Autodesk Fusion 360 part; units mm, degrees
(part 3 of 4)
sketch "Sketch2" plane through (0, 0, -3.5) normal (0, 0, -1) x (1, 0, 0)
  line L0 (7.3822, -60.9328) -> (7.3822, -58.9338)
  line L1 (7.3822, -58.9338) -> (21.3817, -58.9338)
  line L2 (21.3817, -58.9338) -> (21.3817, -60.9328)
  line L3 (21.3817, -60.9328) -> (22.1809, -60.9328)
  line L4 (22.1809, -60.9328) -> (22.1809, -64.0334)
  line L5 (22.1809, -64.0334) -> (21.3817, -64.0334)
  line L6 (21.3817, -64.0334) -> (21.3817, -69.8334)
  line L7 (21.3817, -69.8334) -> (22.1809, -69.8334)
  line L8 (22.1809, -69.8334) -> (22.1809, -72.9326)
  line L9 (22.1809, -72.9326) -> (21.3817, -72.9326)
  line L10 (21.3817, -72.9326) -> (21.3817, -74.9331)
  line L11 (21.3817, -74.9331) -> (7.3822, -74.9331)
  line L12 (7.3822, -74.9331) -> (7.3822, -72.9326)
  line L13 (7.3822, -72.9326) -> (6.5815, -72.9326)
  line L14 (6.5815, -72.9326) -> (6.5815, -69.8334)
  line L15 (6.5815, -69.8334) -> (7.3822, -69.8334)
  line L16 (7.3822, -69.8334) -> (7.3822, -64.0334)
  line L17 (7.3822, -64.0334) -> (6.5815, -64.0334)
  line L18 (6.5815, -64.0334) -> (6.5815, -60.9328)
  line L19 (6.5815, -60.9328) -> (7.3822, -60.9328)
  line L20 (124.062, -3.7827) -> (124.062, -1.7836)
  line L21 (124.062, -1.7836) -> (138.063, -1.7836)
  line L22 (138.063, -1.7836) -> (138.063, -3.7827)
  line L23 (138.063, -3.7827) -> (138.862, -3.7827)
  line L24 (138.862, -3.7827) -> (138.862, -6.8833)
  line L25 (138.862, -6.8833) -> (138.063, -6.8833)
  line L26 (138.063, -6.8833) -> (138.063, -7.4841)
  line L27 (138.063, -7.4841) -> (177.687, -7.4841)
  line L28 (177.687, -7.4841) -> (177.687, -3.0138)
  line L29 (177.687, -3.0138) -> (179.412, -3.0138)
  line L30 (179.412, -3.0138) -> (179.412, -1.8135)
  line L31 (179.412, -1.8135) -> (182.713, -1.8135)
  line L32 (182.713, -1.8135) -> (182.713, -3.0138)
  line L33 (182.713, -3.0138) -> (184.438, -3.0138)
  line L34 (184.438, -3.0138) -> (184.438, -9.2838)
  line L35 (184.438, -9.2838) -> (185.262, -9.2838)
  line L36 (185.262, -9.2838) -> (185.262, -12.0826)
  line L37 (185.262, -12.0826) -> (184.438, -12.0826)
  line L38 (184.438, -12.0826) -> (184.438, -15.3128)
  line L39 (184.438, -15.3128) -> (177.687, -15.3128)
  line L40 (177.687, -15.3128) -> (177.687, -12.0826)
  line L41 (177.687, -12.0826) -> (138.063, -12.0826)
  line L42 (138.063, -12.0826) -> (138.063, -12.6848)
  line L43 (138.063, -12.6848) -> (138.862, -12.6848)
  line L44 (138.862, -12.6848) -> (138.862, -15.7827)
  line L45 (138.862, -15.7827) -> (138.063, -15.7827)
  line L46 (138.063, -15.7827) -> (138.063, -17.7831)
  line L47 (138.063, -17.7831) -> (124.062, -17.7831)
  line L48 (124.062, -17.7831) -> (124.062, -15.7827)
  line L49 (124.062, -15.7827) -> (123.263, -15.7827)
  line L50 (123.263, -15.7827) -> (123.263, -12.6848)
  line L51 (123.263, -12.6848) -> (124.062, -12.6848)
  line L52 (124.062, -12.6848) -> (124.062, -12.0826)
  line L53 (124.062, -12.0826) -> (84.4381, -12.0826)
  line L54 (84.4381, -12.0826) -> (84.4381, -15.3128)
  line L55 (84.4381, -15.3128) -> (77.687, -15.3128)
  line L56 (77.687, -15.3128) -> (77.687, -12.0826)
  line L57 (77.687, -12.0826) -> (76.8629, -12.0826)
  line L58 (76.8629, -12.0826) -> (76.8629, -9.2838)
  line L59 (76.8629, -9.2838) -> (77.687, -9.2838)
  line L60 (77.687, -9.2838) -> (77.687, -3.0138)
  line L61 (77.687, -3.0138) -> (79.412, -3.0138)
  line L62 (79.412, -3.0138) -> (79.412, -1.8135)
  line L63 (79.412, -1.8135) -> (82.7126, -1.8135)
  line L64 (82.7126, -1.8135) -> (82.7126, -3.0138)
  line L65 (82.7126, -3.0138) -> (84.4381, -3.0138)
  line L66 (84.4381, -3.0138) -> (84.4381, -7.4841)
  line L67 (84.4381, -7.4841) -> (124.062, -7.4841)
  line L68 (124.062, -7.4841) -> (124.062, -6.8833)
  line L69 (124.062, -6.8833) -> (123.263, -6.8833)
  line L70 (123.263, -6.8833) -> (123.263, -3.7827)
  line L71 (123.263, -3.7827) -> (124.062, -3.7827)
  line L72 (88.3447, -60.9328) -> (88.3447, -58.9338)
  line L73 (88.3447, -58.9338) -> (102.344, -58.9338)
  line L74 (102.344, -58.9338) -> (102.344, -60.9328)
  line L75 (102.344, -60.9328) -> (103.145, -60.9328)
  line L76 (103.145, -60.9328) -> (103.145, -64.0334)
  line L77 (103.145, -64.0334) -> (102.344, -64.0334)
  line L78 (102.344, -64.0334) -> (102.344, -69.8334)
  line L79 (102.344, -69.8334) -> (103.145, -69.8334)
  line L80 (103.145, -69.8334) -> (103.145, -72.9326)
  line L81 (103.145, -72.9326) -> (102.344, -72.9326)
  line L82 (102.344, -72.9326) -> (102.344, -74.9331)
  line L83 (102.344, -74.9331) -> (88.3447, -74.9331)
  line L84 (88.3447, -74.9331) -> (88.3447, -72.9326)
  line L85 (88.3447, -72.9326) -> (87.5439, -72.9326)
  line L86 (87.5439, -72.9326) -> (87.5439, -69.8334)
  line L87 (87.5439, -69.8334) -> (88.3447, -69.8334)
  line L88 (88.3447, -69.8334) -> (88.3447, -64.0334)
  line L89 (88.3447, -64.0334) -> (87.5439, -64.0334)
  line L90 (87.5439, -64.0334) -> (87.5439, -60.9328)
  line L91 (87.5439, -60.9328) -> (88.3447, -60.9328)
  line L92 (288.37, -41.8828) -> (288.37, -39.8838)
  line L93 (288.37, -39.8838) -> (302.369, -39.8838)
  line L94 (302.369, -39.8838) -> (302.369, -41.8828)
  line L95 (302.369, -41.8828) -> (303.17, -41.8828)
  line L96 (303.17, -41.8828) -> (303.17, -44.9834)
  line L97 (303.17, -44.9834) -> (302.369, -44.9834)
  line L98 (302.369, -44.9834) -> (302.369, -50.7834)
  line L99 (302.369, -50.7834) -> (303.17, -50.7834)
  line L100 (303.17, -50.7834) -> (303.17, -53.8826)
  line L101 (303.17, -53.8826) -> (302.369, -53.8826)
  line L102 (302.369, -53.8826) -> (302.369, -55.8831)
  line L103 (302.369, -55.8831) -> (288.37, -55.8831)
  line L104 (288.37, -55.8831) -> (288.37, -53.8826)
  line L105 (288.37, -53.8826) -> (287.569, -53.8826)
  line L106 (287.569, -53.8826) -> (287.569, -50.7834)
  line L107 (287.569, -50.7834) -> (288.37, -50.7834)
  line L108 (288.37, -50.7834) -> (288.37, -44.9834)
  line L109 (288.37, -44.9834) -> (287.569, -44.9834)
  line L110 (287.569, -44.9834) -> (287.569, -41.8828)
  line L111 (287.569, -41.8828) -> (288.37, -41.8828)
  line L112 (21.6697, -79.9828) -> (21.6697, -77.9838)
  line L113 (21.6697, -77.9838) -> (35.669, -77.9838)
  line L114 (35.669, -77.9838) -> (35.669, -79.9828)
  line L115 (35.669, -79.9828) -> (36.4698, -79.9828)
  line L116 (36.4698, -79.9828) -> (36.4698, -83.0834)
  line L117 (36.4698, -83.0834) -> (35.669, -83.0834)
  line L118 (35.669, -83.0834) -> (35.669, -88.8834)
  line L119 (35.669, -88.8834) -> (36.4698, -88.8834)
  line L120 (36.4698, -88.8834) -> (36.4698, -91.9826)
  line L121 (36.4698, -91.9826) -> (35.669, -91.9826)
  line L122 (35.669, -91.9826) -> (35.669, -93.9831)
  line L123 (35.669, -93.9831) -> (21.6697, -93.9831)
  line L124 (21.6697, -93.9831) -> (21.6697, -91.9826)
  line L125 (21.6697, -91.9826) -> (20.869, -91.9826)
  line L126 (20.869, -91.9826) -> (20.869, -88.8834)
  line L127 (20.869, -88.8834) -> (21.6697, -88.8834)
  line L128 (21.6697, -88.8834) -> (21.6697, -83.0834)
  line L129 (21.6697, -83.0834) -> (20.869, -83.0834)
  line L130 (20.869, -83.0834) -> (20.869, -79.9828)
  line L131 (20.869, -79.9828) -> (21.6697, -79.9828)
  line L132 (259.795, -79.9828) -> (259.795, -77.9838)
  line L133 (259.795, -77.9838) -> (273.794, -77.9838)
  line L134 (273.794, -77.9838) -> (273.794, -79.9828)
  line L135 (273.794, -79.9828) -> (274.595, -79.9828)
  line L136 (274.595, -79.9828) -> (274.595, -83.0834)
  line L137 (274.595, -83.0834) -> (273.794, -83.0834)
  line L138 (273.794, -83.0834) -> (273.794, -83.6828)
  line L139 (273.794, -83.6828) -> (275.32, -83.6828)
  line L140 (275.32, -83.6828) -> (275.32, -79.2138)
  line L141 (275.32, -79.2138) -> (277.045, -79.2138)
  line L142 (277.045, -79.2138) -> (277.045, -78.0136)
  line L143 (277.045, -78.0136) -> (280.344, -78.0136)
  line L144 (280.344, -78.0136) -> (280.344, -79.2138)
  line L145 (280.344, -79.2138) -> (282.069, -79.2138)
  line L146 (282.069, -79.2138) -> (282.069, -85.4837)
  line L147 (282.069, -85.4837) -> (282.895, -85.4837)
  line L148 (282.895, -85.4837) -> (282.895, -88.2826)
  line L149 (282.895, -88.2826) -> (282.069, -88.2826)
  line L150 (282.069, -88.2826) -> (282.069, -91.5127)
  line L151 (282.069, -91.5127) -> (275.32, -91.5127)
  line L152 (275.32, -91.5127) -> (275.32, -88.2826)
  line L153 (275.32, -88.2826) -> (273.794, -88.2826)
  line L154 (273.794, -88.2826) -> (273.794, -88.8834)
  line L155 (273.794, -88.8834) -> (274.595, -88.8834)
  line L156 (274.595, -88.8834) -> (274.595, -91.9826)
  line L157 (274.595, -91.9826) -> (273.794, -91.9826)
  line L158 (273.794, -91.9826) -> (273.794, -93.9831)
  line L159 (273.794, -93.9831) -> (259.795, -93.9831)
  line L160 (259.795, -93.9831) -> (259.795, -91.9826)
  line L161 (259.795, -91.9826) -> (258.994, -91.9826)
  line L162 (258.994, -91.9826) -> (258.994, -88.8834)
  line L163 (258.994, -88.8834) -> (259.795, -88.8834)
  line L164 (259.795, -88.8834) -> (259.795, -88.2826)
  line L165 (259.795, -88.2826) -> (258.269, -88.2826)
  line L166 (258.269, -88.2826) -> (258.269, -91.5127)
  line L167 (258.269, -91.5127) -> (251.52, -91.5127)
  line L168 (251.52, -91.5127) -> (251.52, -88.2826)
  line L169 (251.52, -88.2826) -> (250.694, -88.2826)
  line L170 (250.694, -88.2826) -> (250.694, -85.4837)
  line L171 (250.694, -85.4837) -> (251.52, -85.4837)
  line L172 (251.52, -85.4837) -> (251.52, -79.2138)
  line L173 (251.52, -79.2138) -> (253.243, -79.2138)
  line L174 (253.243, -79.2138) -> (253.243, -78.0136)
  line L175 (253.243, -78.0136) -> (256.544, -78.0136)
  line L176 (256.544, -78.0136) -> (256.544, -79.2138)
  line L177 (256.544, -79.2138) -> (258.269, -79.2138)
  line L178 (258.269, -79.2138) -> (258.269, -83.6828)
  line L179 (258.269, -83.6828) -> (259.795, -83.6828)
  line L180 (259.795, -83.6828) -> (259.795, -83.0834)
  line L181 (259.795, -83.0834) -> (258.994, -83.0834)
  line L182 (258.994, -83.0834) -> (258.994, -79.9828)
  line L183 (258.994, -79.9828) -> (259.795, -79.9828)
  line L184 (288.37, -60.9328) -> (288.37, -58.9338)
  line L185 (288.37, -58.9338) -> (302.369, -58.9338)
  line L186 (302.369, -58.9338) -> (302.369, -60.9328)
  line L187 (302.369, -60.9328) -> (303.17, -60.9328)
  line L188 (303.17, -60.9328) -> (303.17, -64.0334)
  line L189 (303.17, -64.0334) -> (302.369, -64.0334)
  line L190 (302.369, -64.0334) -> (302.369, -69.8334)
  line L191 (302.369, -69.8334) -> (303.17, -69.8334)
  line L192 (303.17, -69.8334) -> (303.17, -72.9326)
  line L193 (303.17, -72.9326) -> (302.369, -72.9326)
  line L194 (302.369, -72.9326) -> (302.369, -74.9331)
  line L195 (302.369, -74.9331) -> (288.37, -74.9331)
  line L196 (288.37, -74.9331) -> (288.37, -72.9326)
  line L197 (288.37, -72.9326) -> (287.569, -72.9326)
  line L198 (287.569, -72.9326) -> (287.569, -69.8334)
  line L199 (287.569, -69.8334) -> (288.37, -69.8334)
  line L200 (288.37, -69.8334) -> (288.37, -64.0334)
  line L201 (288.37, -64.0334) -> (287.569, -64.0334)
  line L202 (287.569, -64.0334) -> (287.569, -60.9328)
  line L203 (287.569, -60.9328) -> (288.37, -60.9328)
  line L204 (40.7197, -79.9828) -> (40.7197, -77.9838)
  line L205 (40.7197, -77.9838) -> (54.719, -77.9838)
  line L206 (54.719, -77.9838) -> (54.719, -79.9828)
  line L207 (54.719, -79.9828) -> (55.5198, -79.9828)
  line L208 (55.5198, -79.9828) -> (55.5198, -83.0834)
  line L209 (55.5198, -83.0834) -> (54.719, -83.0834)
  line L210 (54.719, -83.0834) -> (54.719, -88.8834)
  line L211 (54.719, -88.8834) -> (55.5198, -88.8834)
  line L212 (55.5198, -88.8834) -> (55.5198, -91.9826)
  line L213 (55.5198, -91.9826) -> (54.719, -91.9826)
  line L214 (54.719, -91.9826) -> (54.719, -93.9831)
  line L215 (54.719, -93.9831) -> (40.7197, -93.9831)
  line L216 (40.7197, -93.9831) -> (40.7197, -91.9826)
  line L217 (40.7197, -91.9826) -> (39.9189, -91.9826)
  line L218 (39.9189, -91.9826) -> (39.9189, -88.8834)
  line L219 (39.9189, -88.8834) -> (40.7197, -88.8834)
  line L220 (40.7197, -88.8834) -> (40.7197, -83.0834)
  line L221 (40.7197, -83.0834) -> (39.9189, -83.0834)
  line L222 (39.9189, -83.0834) -> (39.9189, -79.9828)
  line L223 (39.9189, -79.9828) -> (40.7197, -79.9828)
  line L224 (5.0009, -3.7827) -> (5.0009, -1.7836)
  line L225 (5.0009, -1.7836) -> (19.0004, -1.7836)
  line L226 (19.0004, -1.7836) -> (19.0004, -3.7827)
  line L227 (19.0004, -3.7827) -> (19.801, -3.7827)
  line L228 (19.801, -3.7827) -> (19.801, -6.8833)
  line L229 (19.801, -6.8833) -> (19.0004, -6.8833)
  line L230 (19.0004, -6.8833) -> (19.0004, -12.6848)
  line L231 (19.0004, -12.6848) -> (19.801, -12.6848)
  line L232 (19.801, -12.6848) -> (19.801, -15.7827)
  line L233 (19.801, -15.7827) -> (19.0004, -15.7827)
  line L234 (19.0004, -15.7827) -> (19.0004, -17.7831)
  line L235 (19.0004, -17.7831) -> (5.0009, -17.7831)
  line L236 (5.0009, -17.7831) -> (5.0009, -15.7827)
  line L237 (5.0009, -15.7827) -> (4.2003, -15.7827)
  line L238 (4.2003, -15.7827) -> (4.2003, -12.6848)
  line L239 (4.2003, -12.6848) -> (5.0009, -12.6848)
  line L240 (5.0009, -12.6848) -> (5.0009, -6.8833)
  line L241 (5.0009, -6.8833) -> (4.2003, -6.8833)
  line L242 (4.2003, -6.8833) -> (4.2003, -3.7827)
  line L243 (4.2003, -3.7827) -> (5.0009, -3.7827)
  line L244 (202.645, -60.9328) -> (202.645, -58.9338)
  line L245 (202.645, -58.9338) -> (216.644, -58.9338)
  line L246 (216.644, -58.9338) -> (216.644, -60.9328)
  line L247 (216.644, -60.9328) -> (217.445, -60.9328)
  line L248 (217.445, -60.9328) -> (217.445, -64.0334)
  line L249 (217.445, -64.0334) -> (216.644, -64.0334)
  line L250 (216.644, -64.0334) -> (216.644, -69.8334)
  line L251 (216.644, -69.8334) -> (217.445, -69.8334)
  line L252 (217.445, -69.8334) -> (217.445, -72.9326)
  line L253 (217.445, -72.9326) -> (216.644, -72.9326)
  line L254 (216.644, -72.9326) -> (216.644, -74.9331)
  line L255 (216.644, -74.9331) -> (202.645, -74.9331)
  line L256 (202.645, -74.9331) -> (202.645, -72.9326)
  line L257 (202.645, -72.9326) -> (201.844, -72.9326)
  line L258 (201.844, -72.9326) -> (201.844, -69.8334)
  line L259 (201.844, -69.8334) -> (202.645, -69.8334)
  line L260 (202.645, -69.8334) -> (202.645, -64.0334)
  line L261 (202.645, -64.0334) -> (201.844, -64.0334)
  line L262 (201.844, -64.0334) -> (201.844, -60.9328)
  line L263 (201.844, -60.9328) -> (202.645, -60.9328)
  line L264 (288.37, -79.9828) -> (288.37, -77.9838)
  line L265 (288.37, -77.9838) -> (302.369, -77.9838)
  line L266 (302.369, -77.9838) -> (302.369, -79.9828)
  line L267 (302.369, -79.9828) -> (303.17, -79.9828)
  line L268 (303.17, -79.9828) -> (303.17, -83.0834)
  line L269 (303.17, -83.0834) -> (302.369, -83.0834)
  line L270 (302.369, -83.0834) -> (302.369, -88.8834)
  line L271 (302.369, -88.8834) -> (303.17, -88.8834)
  line L272 (303.17, -88.8834) -> (303.17, -91.9826)
  line L273 (303.17, -91.9826) -> (302.369, -91.9826)
  line L274 (302.369, -91.9826) -> (302.369, -93.9831)
  line L275 (302.369, -93.9831) -> (288.37, -93.9831)
  line L276 (288.37, -93.9831) -> (288.37, -91.9826)
  line L277 (288.37, -91.9826) -> (287.569, -91.9826)
  line L278 (287.569, -91.9826) -> (287.569, -88.8834)
  line L279 (287.569, -88.8834) -> (288.37, -88.8834)
  line L280 (288.37, -88.8834) -> (288.37, -83.0834)
  line L281 (288.37, -83.0834) -> (287.569, -83.0834)
  line L282 (287.569, -83.0834) -> (287.569, -79.9828)
  line L283 (287.569, -79.9828) -> (288.37, -79.9828)
  line L284 (212.17, -79.9828) -> (212.17, -77.9838)
  line L285 (212.17, -77.9838) -> (226.169, -77.9838)
  line L286 (226.169, -77.9838) -> (226.169, -79.9828)
  line L287 (226.169, -79.9828) -> (226.97, -79.9828)
  line L288 (226.97, -79.9828) -> (226.97, -83.0834)
  line L289 (226.97, -83.0834) -> (226.169, -83.0834)
  line L290 (226.169, -83.0834) -> (226.169, -88.8834)
  line L291 (226.169, -88.8834) -> (226.97, -88.8834)
  line L292 (226.97, -88.8834) -> (226.97, -91.9826)
  line L293 (226.97, -91.9826) -> (226.169, -91.9826)
  line L294 (226.169, -91.9826) -> (226.169, -93.9831)
  line L295 (226.169, -93.9831) -> (212.17, -93.9831)
  line L296 (212.17, -93.9831) -> (212.17, -91.9826)
  line L297 (212.17, -91.9826) -> (211.369, -91.9826)
  line L298 (211.369, -91.9826) -> (211.369, -88.8834)
  line L299 (211.369, -88.8834) -> (212.17, -88.8834)
  line L300 (212.17, -88.8834) -> (212.17, -83.0834)
  line L301 (212.17, -83.0834) -> (211.369, -83.0834)
  line L302 (211.369, -83.0834) -> (211.369, -79.9828)
  line L303 (211.369, -79.9828) -> (212.17, -79.9828)
  line L304 (174.07, -79.9828) -> (174.07, -77.9838)
  line L305 (174.07, -77.9838) -> (188.069, -77.9838)
  line L306 (188.069, -77.9838) -> (188.069, -79.9828)
  line L307 (188.069, -79.9828) -> (188.87, -79.9828)
  line L308 (188.87, -79.9828) -> (188.87, -83.0834)
  line L309 (188.87, -83.0834) -> (188.069, -83.0834)
  line L310 (188.069, -83.0834) -> (188.069, -88.8834)
  line L311 (188.069, -88.8834) -> (188.87, -88.8834)
  line L312 (188.87, -88.8834) -> (188.87, -91.9826)
  line L313 (188.87, -91.9826) -> (188.069, -91.9826)
  line L314 (188.069, -91.9826) -> (188.069, -93.9831)
  line L315 (188.069, -93.9831) -> (174.07, -93.9831)
  line L316 (174.07, -93.9831) -> (174.07, -91.9826)
  line L317 (174.07, -91.9826) -> (173.269, -91.9826)
  line L318 (173.269, -91.9826) -> (173.269, -88.8834)
  line L319 (173.269, -88.8834) -> (174.07, -88.8834)
  line L320 (174.07, -88.8834) -> (174.07, -83.0834)
  line L321 (174.07, -83.0834) -> (173.269, -83.0834)
  line L322 (173.269, -83.0834) -> (173.269, -79.9828)
  line L323 (173.269, -79.9828) -> (174.07, -79.9828)
  line L324 (116.918, -79.9828) -> (116.918, -77.9838)
  line L325 (116.918, -77.9838) -> (130.919, -77.9838)
  line L326 (130.919, -77.9838) -> (130.919, -79.9828)
  line L327 (130.919, -79.9828) -> (131.72, -79.9828)
  line L328 (131.72, -79.9828) -> (131.72, -83.0834)
  line L329 (131.72, -83.0834) -> (130.919, -83.0834)
  line L330 (130.919, -83.0834) -> (130.919, -88.8834)
  line L331 (130.919, -88.8834) -> (131.72, -88.8834)
  line L332 (131.72, -88.8834) -> (131.72, -91.9826)
  line L333 (131.72, -91.9826) -> (130.919, -91.9826)
  line L334 (130.919, -91.9826) -> (130.919, -93.9831)
  line L335 (130.919, -93.9831) -> (116.918, -93.9831)
  line L336 (116.918, -93.9831) -> (116.918, -91.9826)
  line L337 (116.918, -91.9826) -> (116.119, -91.9826)
  line L338 (116.119, -91.9826) -> (116.119, -88.8834)
  line L339 (116.119, -88.8834) -> (116.918, -88.8834)
  line L340 (116.918, -88.8834) -> (116.918, -83.0834)
  line L341 (116.918, -83.0834) -> (116.119, -83.0834)
  line L342 (116.119, -83.0834) -> (116.119, -79.9828)
  line L343 (116.119, -79.9828) -> (116.918, -79.9828)
  line L344 (269.32, -3.7827) -> (269.32, -1.7836)
  line L345 (269.32, -1.7836) -> (283.319, -1.7836)
  line L346 (283.319, -1.7836) -> (283.319, -3.7827)
  line L347 (283.319, -3.7827) -> (284.12, -3.7827)
  line L348 (284.12, -3.7827) -> (284.12, -6.8833)
  line L349 (284.12, -6.8833) -> (283.319, -6.8833)
  line L350 (283.319, -6.8833) -> (283.319, -12.6848)
  line L351 (283.319, -12.6848) -> (284.12, -12.6848)
  line L352 (284.12, -12.6848) -> (284.12, -15.7827)
  line L353 (284.12, -15.7827) -> (283.319, -15.7827)
  line L354 (283.319, -15.7827) -> (283.319, -17.7831)
  line L355 (283.319, -17.7831) -> (269.32, -17.7831)
  line L356 (269.32, -17.7831) -> (269.32, -15.7827)
  line L357 (269.32, -15.7827) -> (268.519, -15.7827)
  line L358 (268.519, -15.7827) -> (268.519, -12.6848)
  line L359 (268.519, -12.6848) -> (269.32, -12.6848)
  line L360 (269.32, -12.6848) -> (269.32, -6.8833)
  line L361 (269.32, -6.8833) -> (268.519, -6.8833)
  line L362 (268.519, -6.8833) -> (268.519, -3.7827)
  line L363 (268.519, -3.7827) -> (269.32, -3.7827)
  line L364 (212.17, -3.7827) -> (212.17, -1.7836)
  line L365 (212.17, -1.7836) -> (226.169, -1.7836)
  line L366 (226.169, -1.7836) -> (226.169, -3.7827)
  line L367 (226.169, -3.7827) -> (226.97, -3.7827)
  line L368 (226.97, -3.7827) -> (226.97, -6.8833)
  line L369 (226.97, -6.8833) -> (226.169, -6.8833)
  line L370 (226.169, -6.8833) -> (226.169, -12.6848)
  line L371 (226.169, -12.6848) -> (226.97, -12.6848)
  line L372 (226.97, -12.6848) -> (226.97, -15.7827)
  line L373 (226.97, -15.7827) -> (226.169, -15.7827)
  line L374 (226.169, -15.7827) -> (226.169, -17.7831)
  line L375 (226.169, -17.7831) -> (212.17, -17.7831)
  line L376 (212.17, -17.7831) -> (212.17, -15.7827)
  line L377 (212.17, -15.7827) -> (211.369, -15.7827)
  line L378 (211.369, -15.7827) -> (211.369, -12.6848)
  line L379 (211.369, -12.6848) -> (212.17, -12.6848)
  line L380 (212.17, -12.6848) -> (212.17, -6.8833)
  line L381 (212.17, -6.8833) -> (211.369, -6.8833)
  line L382 (211.369, -6.8833) -> (211.369, -3.7827)
  line L383 (211.369, -3.7827) -> (212.17, -3.7827)
  line L384 (288.37, -3.7827) -> (288.37, -1.7836)
  line L385 (288.37, -1.7836) -> (302.369, -1.7836)
  line L386 (302.369, -1.7836) -> (302.369, -3.7827)
  line L387 (302.369, -3.7827) -> (303.17, -3.7827)
  line L388 (303.17, -3.7827) -> (303.17, -6.8833)
  line L389 (303.17, -6.8833) -> (302.369, -6.8833)
  line L390 (302.369, -6.8833) -> (302.369, -12.6848)
  line L391 (302.369, -12.6848) -> (303.17, -12.6848)
  line L392 (303.17, -12.6848) -> (303.17, -15.7827)
  line L393 (303.17, -15.7827) -> (302.369, -15.7827)
  line L394 (302.369, -15.7827) -> (302.369, -17.7831)
  line L395 (302.369, -17.7831) -> (288.37, -17.7831)
  line L396 (288.37, -17.7831) -> (288.37, -15.7827)
  line L397 (288.37, -15.7827) -> (287.569, -15.7827)
  line L398 (287.569, -15.7827) -> (287.569, -12.6848)
  line L399 (287.569, -12.6848) -> (288.37, -12.6848)
  line L400 (288.37, -12.6848) -> (288.37, -6.8833)
  line L401 (288.37, -6.8833) -> (287.569, -6.8833)
  line L402 (287.569, -6.8833) -> (287.569, -3.7827)
  line L403 (287.569, -3.7827) -> (288.37, -3.7827)
  line L404 (45.4822, -22.8327) -> (45.4822, -20.8336)
  line L405 (45.4822, -20.8336) -> (59.4815, -20.8336)
  line L406 (59.4815, -20.8336) -> (59.4815, -22.8327)
  line L407 (59.4815, -22.8327) -> (60.2809, -22.8327)
  line L408 (60.2809, -22.8327) -> (60.2809, -25.9333)
  line L409 (60.2809, -25.9333) -> (59.4815, -25.9333)
  line L410 (59.4815, -25.9333) -> (59.4815, -31.7348)
  line L411 (59.4815, -31.7348) -> (60.2809, -31.7348)
  line L412 (60.2809, -31.7348) -> (60.2809, -34.8327)
  line L413 (60.2809, -34.8327) -> (59.4815, -34.8327)
  line L414 (59.4815, -34.8327) -> (59.4815, -36.833)
  line L415 (59.4815, -36.833) -> (45.4822, -36.833)
  line L416 (45.4822, -36.833) -> (45.4822, -34.8327)
  line L417 (45.4822, -34.8327) -> (44.6814, -34.8327)
  line L418 (44.6814, -34.8327) -> (44.6814, -31.7348)
  line L419 (44.6814, -31.7348) -> (45.4822, -31.7348)
  line L420 (45.4822, -31.7348) -> (45.4822, -25.9333)
  line L421 (45.4822, -25.9333) -> (44.6814, -25.9333)
  line L422 (44.6814, -25.9333) -> (44.6814, -22.8327)
  line L423 (44.6814, -22.8327) -> (45.4822, -22.8327)
  line L424 (216.932, -22.8327) -> (216.932, -20.8336)
  line L425 (216.932, -20.8336) -> (230.932, -20.8336)
  line L426 (230.932, -20.8336) -> (230.932, -22.8327)
  line L427 (230.932, -22.8327) -> (231.731, -22.8327)
  line L428 (231.731, -22.8327) -> (231.731, -25.9333)
  line L429 (231.731, -25.9333) -> (230.932, -25.9333)
  line L430 (230.932, -25.9333) -> (230.932, -31.7348)
  line L431 (230.932, -31.7348) -> (231.731, -31.7348)
  line L432 (231.731, -31.7348) -> (231.731, -34.8327)
  line L433 (231.731, -34.8327) -> (230.932, -34.8327)
  line L434 (230.932, -34.8327) -> (230.932, -36.833)
  line L435 (230.932, -36.833) -> (216.932, -36.833)
  line L436 (216.932, -36.833) -> (216.932, -34.8327)
  line L437 (216.932, -34.8327) -> (216.131, -34.8327)
  line L438 (216.131, -34.8327) -> (216.131, -31.7348)
  line L439 (216.131, -31.7348) -> (216.932, -31.7348)
  line L440 (216.932, -31.7348) -> (216.932, -25.9333)
  line L441 (216.932, -25.9333) -> (216.131, -25.9333)
  line L442 (216.131, -25.9333) -> (216.131, -22.8327)
  line L443 (216.131, -22.8327) -> (216.932, -22.8327)
  line L444 (197.882, -22.8327) -> (197.882, -20.8336)
  line L445 (197.882, -20.8336) -> (211.882, -20.8336)
  line L446 (211.882, -20.8336) -> (211.882, -22.8327)
  line L447 (211.882, -22.8327) -> (212.681, -22.8327)
  line L448 (212.681, -22.8327) -> (212.681, -25.9333)
  line L449 (212.681, -25.9333) -> (211.882, -25.9333)
  line L450 (211.882, -25.9333) -> (211.882, -31.7348)
  line L451 (211.882, -31.7348) -> (212.681, -31.7348)
  line L452 (212.681, -31.7348) -> (212.681, -34.8327)
  line L453 (212.681, -34.8327) -> (211.882, -34.8327)
  line L454 (211.882, -34.8327) -> (211.882, -36.833)
  line L455 (211.882, -36.833) -> (197.882, -36.833)
  line L456 (197.882, -36.833) -> (197.882, -34.8327)
  line L457 (197.882, -34.8327) -> (197.081, -34.8327)
  line L458 (197.081, -34.8327) -> (197.081, -31.7348)
  line L459 (197.081, -31.7348) -> (197.882, -31.7348)
  line L460 (197.882, -31.7348) -> (197.882, -25.9333)
  line L461 (197.882, -25.9333) -> (197.081, -25.9333)
  line L462 (197.081, -25.9333) -> (197.081, -22.8327)
  line L463 (197.081, -22.8327) -> (197.882, -22.8327)
  line L464 (28.812, -3.7827) -> (28.812, -1.7836)
  line L465 (28.812, -1.7836) -> (42.8128, -1.7836)
  line L466 (42.8128, -1.7836) -> (42.8128, -3.7827)
  line L467 (42.8128, -3.7827) -> (43.6122, -3.7827)
  line L468 (43.6122, -3.7827) -> (43.6122, -6.8833)
  line L469 (43.6122, -6.8833) -> (42.8128, -6.8833)
  line L470 (42.8128, -6.8833) -> (42.8128, -12.6848)
  line L471 (42.8128, -12.6848) -> (43.6122, -12.6848)
  line L472 (43.6122, -12.6848) -> (43.6122, -15.7827)
  line L473 (43.6122, -15.7827) -> (42.8128, -15.7827)
  line L474 (42.8128, -15.7827) -> (42.8128, -17.7831)
  line L475 (42.8128, -17.7831) -> (28.812, -17.7831)
  line L476 (28.812, -17.7831) -> (28.812, -15.7827)
  line L477 (28.812, -15.7827) -> (28.0128, -15.7827)
  line L478 (28.0128, -15.7827) -> (28.0128, -12.6848)
  line L479 (28.0128, -12.6848) -> (28.812, -12.6848)
  line L480 (28.812, -12.6848) -> (28.812, -6.8833)
  line L481 (28.812, -6.8833) -> (28.0128, -6.8833)
  line L482 (28.0128, -6.8833) -> (28.0128, -3.7827)
  line L483 (28.0128, -3.7827) -> (28.812, -3.7827)
  line L484 (93.1072, -41.8828) -> (93.1072, -39.8838)
  line L485 (93.1072, -39.8838) -> (107.107, -39.8838)
  line L486 (107.107, -39.8838) -> (107.107, -41.8828)
  line L487 (107.107, -41.8828) -> (107.906, -41.8828)
  line L488 (107.906, -41.8828) -> (107.906, -44.9834)
  line L489 (107.906, -44.9834) -> (107.107, -44.9834)
  line L490 (107.107, -44.9834) -> (107.107, -50.7834)
  line L491 (107.107, -50.7834) -> (107.906, -50.7834)
  line L492 (107.906, -50.7834) -> (107.906, -53.8826)
  line L493 (107.906, -53.8826) -> (107.107, -53.8826)
  line L494 (107.107, -53.8826) -> (107.107, -55.8831)
  line L495 (107.107, -55.8831) -> (93.1072, -55.8831)
  line L496 (93.1072, -55.8831) -> (93.1072, -53.8826)
  line L497 (93.1072, -53.8826) -> (92.3064, -53.8826)
  line L498 (92.3064, -53.8826) -> (92.3064, -50.7834)
  line L499 (92.3064, -50.7834) -> (93.1072, -50.7834)
  line L500 (93.1072, -50.7834) -> (93.1072, -44.9834)
  line L501 (93.1072, -44.9834) -> (92.3064, -44.9834)
  line L502 (92.3064, -44.9834) -> (92.3064, -41.8828)
  line L503 (92.3064, -41.8828) -> (93.1072, -41.8828)
  line L504 (207.407, -41.8828) -> (207.407, -39.8838)
  line L505 (207.407, -39.8838) -> (221.407, -39.8838)
  line L506 (221.407, -39.8838) -> (221.407, -41.8828)
  line L507 (221.407, -41.8828) -> (222.206, -41.8828)
  line L508 (222.206, -41.8828) -> (222.206, -44.9834)
  line L509 (222.206, -44.9834) -> (221.407, -44.9834)
  line L510 (221.407, -44.9834) -> (221.407, -50.7834)
  line L511 (221.407, -50.7834) -> (222.206, -50.7834)
  line L512 (222.206, -50.7834) -> (222.206, -53.8826)
  line L513 (222.206, -53.8826) -> (221.407, -53.8826)
  line L514 (221.407, -53.8826) -> (221.407, -55.8831)
  line L515 (221.407, -55.8831) -> (207.407, -55.8831)
  line L516 (207.407, -55.8831) -> (207.407, -53.8826)
  line L517 (207.407, -53.8826) -> (206.606, -53.8826)
  line L518 (206.606, -53.8826) -> (206.606, -50.7834)
  line L519 (206.606, -50.7834) -> (207.407, -50.7834)
  line L520 (207.407, -50.7834) -> (207.407, -44.9834)
  line L521 (207.407, -44.9834) -> (206.606, -44.9834)
  line L522 (206.606, -44.9834) -> (206.606, -41.8828)
  line L523 (206.606, -41.8828) -> (207.407, -41.8828)
  line L524 (243.126, -22.8327) -> (243.126, -20.8336)
  line L525 (243.126, -20.8336) -> (257.125, -20.8336)
  line L526 (257.125, -20.8336) -> (257.125, -22.8327)
  line L527 (257.125, -22.8327) -> (257.926, -22.8327)
  line L528 (257.926, -22.8327) -> (257.926, -25.9333)
  line L529 (257.926, -25.9333) -> (257.125, -25.9333)
  line L530 (257.125, -25.9333) -> (257.125, -31.7348)
  line L531 (257.125, -31.7348) -> (257.926, -31.7348)
  line L532 (257.926, -31.7348) -> (257.926, -34.8327)
  line L533 (257.926, -34.8327) -> (257.125, -34.8327)
  line L534 (257.125, -34.8327) -> (257.125, -36.833)
  line L535 (257.125, -36.833) -> (243.126, -36.833)
  line L536 (243.126, -36.833) -> (243.126, -34.8327)
  line L537 (243.126, -34.8327) -> (242.325, -34.8327)
  line L538 (242.325, -34.8327) -> (242.325, -31.7348)
  line L539 (242.325, -31.7348) -> (243.126, -31.7348)
  line L540 (243.126, -31.7348) -> (243.126, -25.9333)
  line L541 (243.126, -25.9333) -> (242.325, -25.9333)
  line L542 (242.325, -25.9333) -> (242.325, -22.8327)
  line L543 (242.325, -22.8327) -> (243.126, -22.8327)
  line L544 (9.762, -41.8828) -> (9.762, -39.8838)
  line L545 (9.762, -39.8838) -> (23.7629, -39.8838)
  line L546 (23.7629, -39.8838) -> (23.7629, -41.8828)
  line L547 (23.7629, -41.8828) -> (24.5622, -41.8828)
  line L548 (24.5622, -41.8828) -> (24.5622, -44.9834)
  line L549 (24.5622, -44.9834) -> (23.7629, -44.9834)
  line L550 (23.7629, -44.9834) -> (23.7629, -50.7834)
  line L551 (23.7629, -50.7834) -> (24.5622, -50.7834)
  line L552 (24.5622, -50.7834) -> (24.5622, -53.8826)
  line L553 (24.5622, -53.8826) -> (23.7629, -53.8826)
  line L554 (23.7629, -53.8826) -> (23.7629, -55.8831)
  line L555 (23.7629, -55.8831) -> (9.762, -55.8831)
  line L556 (9.762, -55.8831) -> (9.762, -53.8826)
  line L557 (9.762, -53.8826) -> (8.9628, -53.8826)
  line L558 (8.9628, -53.8826) -> (8.9628, -50.7834)
  line L559 (8.9628, -50.7834) -> (9.762, -50.7834)
  line L560 (9.762, -50.7834) -> (9.762, -44.9834)
  line L561 (9.762, -44.9834) -> (8.9628, -44.9834)
  line L562 (8.9628, -44.9834) -> (8.9628, -41.8828)
  line L563 (8.9628, -41.8828) -> (9.762, -41.8828)
  line L564 (64.5322, -22.8327) -> (64.5322, -20.8336)
  line L565 (64.5322, -20.8336) -> (78.5315, -20.8336)
  line L566 (78.5315, -20.8336) -> (78.5315, -22.8327)
  line L567 (78.5315, -22.8327) -> (79.3309, -22.8327)
  line L568 (79.3309, -22.8327) -> (79.3309, -25.9333)
  line L569 (79.3309, -25.9333) -> (78.5315, -25.9333)
  line L570 (78.5315, -25.9333) -> (78.5315, -31.7348)
  line L571 (78.5315, -31.7348) -> (79.3309, -31.7348)
  line L572 (79.3309, -31.7348) -> (79.3309, -34.8327)
  line L573 (79.3309, -34.8327) -> (78.5315, -34.8327)
  line L574 (78.5315, -34.8327) -> (78.5315, -36.833)
  line L575 (78.5315, -36.833) -> (64.5322, -36.833)
  line L576 (64.5322, -36.833) -> (64.5322, -34.8327)
  line L577 (64.5322, -34.8327) -> (63.7314, -34.8327)
  line L578 (63.7314, -34.8327) -> (63.7314, -31.7348)
  line L579 (63.7314, -31.7348) -> (64.5322, -31.7348)
  line L580 (64.5322, -31.7348) -> (64.5322, -25.9333)
  line L581 (64.5322, -25.9333) -> (63.7314, -25.9333)
  line L582 (63.7314, -25.9333) -> (63.7314, -22.8327)
  line L583 (63.7314, -22.8327) -> (64.5322, -22.8327)
  line L584 (240.745, -60.9328) -> (240.745, -58.9338)
  line L585 (240.745, -58.9338) -> (254.744, -58.9338)
  line L586 (254.744, -58.9338) -> (254.744, -60.9328)
  line L587 (254.744, -60.9328) -> (255.545, -60.9328)
  line L588 (255.545, -60.9328) -> (255.545, -64.0334)
  line L589 (255.545, -64.0334) -> (254.744, -64.0334)
  line L590 (254.744, -64.0334) -> (254.744, -69.8334)
  line L591 (254.744, -69.8334) -> (255.545, -69.8334)
  line L592 (255.545, -69.8334) -> (255.545, -72.9326)
  line L593 (255.545, -72.9326) -> (254.744, -72.9326)
  line L594 (254.744, -72.9326) -> (254.744, -74.9331)
  line L595 (254.744, -74.9331) -> (240.745, -74.9331)
  line L596 (240.745, -74.9331) -> (240.745, -72.9326)
  line L597 (240.745, -72.9326) -> (239.944, -72.9326)
  line L598 (239.944, -72.9326) -> (239.944, -69.8334)
  line L599 (239.944, -69.8334) -> (240.745, -69.8334)
  line L600 (240.745, -69.8334) -> (240.745, -64.0334)
  line L601 (240.745, -64.0334) -> (239.944, -64.0334)
  line L602 (239.944, -64.0334) -> (239.944, -60.9328)
  line L603 (239.944, -60.9328) -> (240.745, -60.9328)
  line L604 (107.395, -60.9328) -> (107.395, -58.9338)
  line L605 (107.395, -58.9338) -> (121.394, -58.9338)
  line L606 (121.394, -58.9338) -> (121.394, -60.9328)
  line L607 (121.394, -60.9328) -> (122.195, -60.9328)
  line L608 (122.195, -60.9328) -> (122.195, -64.0334)
  line L609 (122.195, -64.0334) -> (121.394, -64.0334)
  line L610 (121.394, -64.0334) -> (121.394, -69.8334)
  line L611 (121.394, -69.8334) -> (122.195, -69.8334)
  line L612 (122.195, -69.8334) -> (122.195, -72.9326)
  line L613 (122.195, -72.9326) -> (121.394, -72.9326)
  line L614 (121.394, -72.9326) -> (121.394, -74.9331)
  line L615 (121.394, -74.9331) -> (107.395, -74.9331)
  line L616 (107.395, -74.9331) -> (107.395, -72.9326)
  line L617 (107.395, -72.9326) -> (106.594, -72.9326)
  line L618 (106.594, -72.9326) -> (106.594, -69.8334)
  line L619 (106.594, -69.8334) -> (107.395, -69.8334)
  line L620 (107.395, -69.8334) -> (107.395, -64.0334)
  line L621 (107.395, -64.0334) -> (106.594, -64.0334)
  line L622 (106.594, -64.0334) -> (106.594, -60.9328)
  line L623 (106.594, -60.9328) -> (107.395, -60.9328)
  line L624 (35.9572, -41.8828) -> (35.9572, -39.8838)
  line L625 (35.9572, -39.8838) -> (49.9565, -39.8838)
  line L626 (49.9565, -39.8838) -> (49.9565, -41.8828)
  line L627 (49.9565, -41.8828) -> (50.7559, -41.8828)
  line L628 (50.7559, -41.8828) -> (50.7559, -44.9834)
  line L629 (50.7559, -44.9834) -> (49.9565, -44.9834)
  line L630 (49.9565, -44.9834) -> (49.9565, -50.7834)
  line L631 (49.9565, -50.7834) -> (50.7559, -50.7834)
  line L632 (50.7559, -50.7834) -> (50.7559, -53.8826)
  line L633 (50.7559, -53.8826) -> (49.9565, -53.8826)
  line L634 (49.9565, -53.8826) -> (49.9565, -55.8831)
  line L635 (49.9565, -55.8831) -> (35.9572, -55.8831)
  line L636 (35.9572, -55.8831) -> (35.9572, -53.8826)
  line L637 (35.9572, -53.8826) -> (35.1565, -53.8826)
  line L638 (35.1565, -53.8826) -> (35.1565, -50.7834)
  line L639 (35.1565, -50.7834) -> (35.9572, -50.7834)
  line L640 (35.9572, -50.7834) -> (35.9572, -44.9834)
  line L641 (35.9572, -44.9834) -> (35.1565, -44.9834)
  line L642 (35.1565, -44.9834) -> (35.1565, -41.8828)
  line L643 (35.1565, -41.8828) -> (35.9572, -41.8828)
  line L644 (52.626, -3.7827) -> (52.626, -1.7836)
  line L645 (52.626, -1.7836) -> (66.6253, -1.7836)
  line L646 (66.6253, -1.7836) -> (66.6253, -3.7827)
  line L647 (66.6253, -3.7827) -> (67.4261, -3.7827)
  line L648 (67.4261, -3.7827) -> (67.4261, -6.8833)
  line L649 (67.4261, -6.8833) -> (66.6253, -6.8833)
  line L650 (66.6253, -6.8833) -> (66.6253, -12.6848)
  line L651 (66.6253, -12.6848) -> (67.4261, -12.6848)
  line L652 (67.4261, -12.6848) -> (67.4261, -15.7827)
  line L653 (67.4261, -15.7827) -> (66.6253, -15.7827)
  line L654 (66.6253, -15.7827) -> (66.6253, -17.7831)
  line L655 (66.6253, -17.7831) -> (52.626, -17.7831)
  line L656 (52.626, -17.7831) -> (52.626, -15.7827)
  line L657 (52.626, -15.7827) -> (51.8252, -15.7827)
  line L658 (51.8252, -15.7827) -> (51.8252, -12.6848)
  line L659 (51.8252, -12.6848) -> (52.626, -12.6848)
  line L660 (52.626, -12.6848) -> (52.626, -6.8833)
  line L661 (52.626, -6.8833) -> (51.8252, -6.8833)
  line L662 (51.8252, -6.8833) -> (51.8252, -3.7827)
  line L663 (51.8252, -3.7827) -> (52.626, -3.7827)
  line L664 (304.895, -0.2577) -> (0.0951, -0.2577)
  line L665 (0.0951, -0.2577) -> (0.0951, -95.5075)
  line L666 (0.0951, -95.5075) -> (304.895, -95.5075)
  line L667 (304.895, -95.5075) -> (304.895, -0.2577)
  line L668 (126.445, -60.9328) -> (126.445, -58.9338)
  line L669 (126.445, -58.9338) -> (140.444, -58.9338)
  line L670 (140.444, -58.9338) -> (140.444, -60.9328)
  line L671 (140.444, -60.9328) -> (141.245, -60.9328)
  line L672 (141.245, -60.9328) -> (141.245, -64.0334)
  line L673 (141.245, -64.0334) -> (140.444, -64.0334)
  line L674 (140.444, -64.0334) -> (140.444, -69.8334)
  line L675 (140.444, -69.8334) -> (141.245, -69.8334)
  line L676 (141.245, -69.8334) -> (141.245, -72.9326)
  line L677 (141.245, -72.9326) -> (140.444, -72.9326)
  line L678 (140.444, -72.9326) -> (140.444, -74.9331)
  line L679 (140.444, -74.9331) -> (126.445, -74.9331)
  line L680 (126.445, -74.9331) -> (126.445, -72.9326)
  line L681 (126.445, -72.9326) -> (125.644, -72.9326)
  line L682 (125.644, -72.9326) -> (125.644, -69.8334)
  line L683 (125.644, -69.8334) -> (126.445, -69.8334)
  line L684 (126.445, -69.8334) -> (126.445, -64.0334)
  line L685 (126.445, -64.0334) -> (125.644, -64.0334)
  line L686 (125.644, -64.0334) -> (125.644, -60.9328)
  line L687 (125.644, -60.9328) -> (126.445, -60.9328)
  line L688 (102.632, -22.8327) -> (102.632, -20.8336)
  line L689 (102.632, -20.8336) -> (116.632, -20.8336)
  line L690 (116.632, -20.8336) -> (116.632, -22.8327)
  line L691 (116.632, -22.8327) -> (117.431, -22.8327)
  line L692 (117.431, -22.8327) -> (117.431, -25.9333)
  line L693 (117.431, -25.9333) -> (116.632, -25.9333)
  line L694 (116.632, -25.9333) -> (116.632, -31.7348)
  line L695 (116.632, -31.7348) -> (117.431, -31.7348)
  line L696 (117.431, -31.7348) -> (117.431, -34.8327)
  line L697 (117.431, -34.8327) -> (116.632, -34.8327)
  line L698 (116.632, -34.8327) -> (116.632, -36.833)
  line L699 (116.632, -36.833) -> (102.632, -36.833)
  line L700 (102.632, -36.833) -> (102.632, -34.8327)
  line L701 (102.632, -34.8327) -> (101.831, -34.8327)
  line L702 (101.831, -34.8327) -> (101.831, -31.7348)
  line L703 (101.831, -31.7348) -> (102.632, -31.7348)
  line L704 (102.632, -31.7348) -> (102.632, -25.9333)
  line L705 (102.632, -25.9333) -> (101.831, -25.9333)
  line L706 (101.831, -25.9333) -> (101.831, -22.8327)
  line L707 (101.831, -22.8327) -> (102.632, -22.8327)
  line L708 (226.457, -41.8828) -> (226.457, -39.8838)
  line L709 (226.457, -39.8838) -> (240.457, -39.8838)
  line L710 (240.457, -39.8838) -> (240.457, -41.8828)
  line L711 (240.457, -41.8828) -> (241.256, -41.8828)
  line L712 (241.256, -41.8828) -> (241.256, -44.9834)
  line L713 (241.256, -44.9834) -> (240.457, -44.9834)
  line L714 (240.457, -44.9834) -> (240.457, -50.7834)
  line L715 (240.457, -50.7834) -> (241.256, -50.7834)
  line L716 (241.256, -50.7834) -> (241.256, -53.8826)
  line L717 (241.256, -53.8826) -> (240.457, -53.8826)
  line L718 (240.457, -53.8826) -> (240.457, -55.8831)
  line L719 (240.457, -55.8831) -> (226.457, -55.8831)
  line L720 (226.457, -55.8831) -> (226.457, -53.8826)
  line L721 (226.457, -53.8826) -> (225.656, -53.8826)
  line L722 (225.656, -53.8826) -> (225.656, -50.7834)
  line L723 (225.656, -50.7834) -> (226.457, -50.7834)
  line L724 (226.457, -50.7834) -> (226.457, -44.9834)
  line L725 (226.457, -44.9834) -> (225.656, -44.9834)
  line L726 (225.656, -44.9834) -> (225.656, -41.8828)
  line L727 (225.656, -41.8828) -> (226.457, -41.8828)
  line L728 (159.782, -22.8327) -> (159.782, -20.8336)
  line L729 (159.782, -20.8336) -> (173.782, -20.8336)
  line L730 (173.782, -20.8336) -> (173.782, -22.8327)
  line L731 (173.782, -22.8327) -> (174.581, -22.8327)
  line L732 (174.581, -22.8327) -> (174.581, -25.9333)
  line L733 (174.581, -25.9333) -> (173.782, -25.9333)
  line L734 (173.782, -25.9333) -> (173.782, -31.7348)
  line L735 (173.782, -31.7348) -> (174.581, -31.7348)
  line L736 (174.581, -31.7348) -> (174.581, -34.8327)
  line L737 (174.581, -34.8327) -> (173.782, -34.8327)
  line L738 (173.782, -34.8327) -> (173.782, -36.833)
  line L739 (173.782, -36.833) -> (159.782, -36.833)
  line L740 (159.782, -36.833) -> (159.782, -34.8327)
  line L741 (159.782, -34.8327) -> (158.981, -34.8327)
  line L742 (158.981, -34.8327) -> (158.981, -31.7348)
  line L743 (158.981, -31.7348) -> (159.782, -31.7348)
  line L744 (159.782, -31.7348) -> (159.782, -25.9333)
  line L745 (159.782, -25.9333) -> (158.981, -25.9333)
  line L746 (158.981, -25.9333) -> (158.981, -22.8327)
  line L747 (158.981, -22.8327) -> (159.782, -22.8327)
  line L748 (112.157, -41.8828) -> (112.157, -39.8838)
  line L749 (112.157, -39.8838) -> (126.157, -39.8838)
  line L750 (126.157, -39.8838) -> (126.157, -41.8828)
  line L751 (126.157, -41.8828) -> (126.956, -41.8828)
  line L752 (126.956, -41.8828) -> (126.956, -44.9834)
  line L753 (126.956, -44.9834) -> (126.157, -44.9834)
  line L754 (126.157, -44.9834) -> (126.157, -50.7834)
  line L755 (126.157, -50.7834) -> (126.956, -50.7834)
  line L756 (126.956, -50.7834) -> (126.956, -53.8826)
  line L757 (126.956, -53.8826) -> (126.157, -53.8826)
  line L758 (126.157, -53.8826) -> (126.157, -55.8831)
  line L759 (126.157, -55.8831) -> (112.157, -55.8831)
  line L760 (112.157, -55.8831) -> (112.157, -53.8826)
  line L761 (112.157, -53.8826) -> (111.356, -53.8826)
  line L762 (111.356, -53.8826) -> (111.356, -50.7834)
  line L763 (111.356, -50.7834) -> (112.157, -50.7834)
  line L764 (112.157, -50.7834) -> (112.157, -44.9834)
  line L765 (112.157, -44.9834) -> (111.356, -44.9834)
  line L766 (111.356, -44.9834) -> (111.356, -41.8828)
  line L767 (111.356, -41.8828) -> (112.157, -41.8828)
  line L768 (140.732, -22.8327) -> (140.732, -20.8336)
  line L769 (140.732, -20.8336) -> (154.732, -20.8336)
  line L770 (154.732, -20.8336) -> (154.732, -22.8327)
  line L771 (154.732, -22.8327) -> (155.531, -22.8327)
  line L772 (155.531, -22.8327) -> (155.531, -25.9333)
  line L773 (155.531, -25.9333) -> (154.732, -25.9333)
  line L774 (154.732, -25.9333) -> (154.732, -31.7348)
  line L775 (154.732, -31.7348) -> (155.531, -31.7348)
  line L776 (155.531, -31.7348) -> (155.531, -34.8327)
  line L777 (155.531, -34.8327) -> (154.732, -34.8327)
  line L778 (154.732, -34.8327) -> (154.732, -36.833)
  line L779 (154.732, -36.833) -> (140.732, -36.833)
  line L780 (140.732, -36.833) -> (140.732, -34.8327)
  line L781 (140.732, -34.8327) -> (139.931, -34.8327)
  line L782 (139.931, -34.8327) -> (139.931, -31.7348)
  line L783 (139.931, -31.7348) -> (140.732, -31.7348)
  line L784 (140.732, -31.7348) -> (140.732, -25.9333)
  line L785 (140.732, -25.9333) -> (139.931, -25.9333)
  line L786 (139.931, -25.9333) -> (139.931, -22.8327)
  line L787 (139.931, -22.8327) -> (140.732, -22.8327)
  line L788 (188.357, -41.8828) -> (188.357, -39.8838)
  line L789 (188.357, -39.8838) -> (202.357, -39.8838)
  line L790 (202.357, -39.8838) -> (202.357, -41.8828)
  line L791 (202.357, -41.8828) -> (203.156, -41.8828)
  line L792 (203.156, -41.8828) -> (203.156, -44.9834)
  line L793 (203.156, -44.9834) -> (202.357, -44.9834)
  line L794 (202.357, -44.9834) -> (202.357, -50.7834)
  line L795 (202.357, -50.7834) -> (203.156, -50.7834)
  line L796 (203.156, -50.7834) -> (203.156, -53.8826)
  line L797 (203.156, -53.8826) -> (202.357, -53.8826)
  line L798 (202.357, -53.8826) -> (202.357, -55.8831)
  line L799 (202.357, -55.8831) -> (188.357, -55.8831)
  line L800 (188.357, -55.8831) -> (188.357, -53.8826)
  line L801 (188.357, -53.8826) -> (187.556, -53.8826)
  line L802 (187.556, -53.8826) -> (187.556, -50.7834)
  line L803 (187.556, -50.7834) -> (188.357, -50.7834)
  line L804 (188.357, -50.7834) -> (188.357, -44.9834)
  line L805 (188.357, -44.9834) -> (187.556, -44.9834)
  line L806 (187.556, -44.9834) -> (187.556, -41.8828)
  line L807 (187.556, -41.8828) -> (188.357, -41.8828)
  line L808 (131.207, -41.8828) -> (131.207, -39.8838)
  line L809 (131.207, -39.8838) -> (145.207, -39.8838)
  line L810 (145.207, -39.8838) -> (145.207, -41.8828)
  line L811 (145.207, -41.8828) -> (146.006, -41.8828)
  line L812 (146.006, -41.8828) -> (146.006, -44.9834)
  line L813 (146.006, -44.9834) -> (145.207, -44.9834)
  line L814 (145.207, -44.9834) -> (145.207, -50.7834)
  line L815 (145.207, -50.7834) -> (146.006, -50.7834)
  line L816 (146.006, -50.7834) -> (146.006, -53.8826)
  line L817 (146.006, -53.8826) -> (145.207, -53.8826)
  line L818 (145.207, -53.8826) -> (145.207, -55.8831)
  line L819 (145.207, -55.8831) -> (131.207, -55.8831)
  line L820 (131.207, -55.8831) -> (131.207, -53.8826)
  line L821 (131.207, -53.8826) -> (130.406, -53.8826)
  line L822 (130.406, -53.8826) -> (130.406, -50.7834)
  line L823 (130.406, -50.7834) -> (131.207, -50.7834)
  line L824 (131.207, -50.7834) -> (131.207, -44.9834)
  line L825 (131.207, -44.9834) -> (130.406, -44.9834)
  line L826 (130.406, -44.9834) -> (130.406, -41.8828)
  line L827 (130.406, -41.8828) -> (131.207, -41.8828)
  line L828 (178.832, -22.8327) -> (178.832, -20.8336)
  line L829 (178.832, -20.8336) -> (192.832, -20.8336)
  line L830 (192.832, -20.8336) -> (192.832, -22.8327)
  line L831 (192.832, -22.8327) -> (193.631, -22.8327)
  line L832 (193.631, -22.8327) -> (193.631, -25.9333)
  line L833 (193.631, -25.9333) -> (192.832, -25.9333)
  line L834 (192.832, -25.9333) -> (192.832, -31.7348)
  line L835 (192.832, -31.7348) -> (193.631, -31.7348)
  line L836 (193.631, -31.7348) -> (193.631, -34.8327)
  line L837 (193.631, -34.8327) -> (192.832, -34.8327)
  line L838 (192.832, -34.8327) -> (192.832, -36.833)
  line L839 (192.832, -36.833) -> (178.832, -36.833)
  line L840 (178.832, -36.833) -> (178.832, -34.8327)
  line L841 (178.832, -34.8327) -> (178.031, -34.8327)
  line L842 (178.031, -34.8327) -> (178.031, -31.7348)
  line L843 (178.031, -31.7348) -> (178.832, -31.7348)
  line L844 (178.832, -31.7348) -> (178.832, -25.9333)
  line L845 (178.832, -25.9333) -> (178.031, -25.9333)
  line L846 (178.031, -25.9333) -> (178.031, -22.8327)
  line L847 (178.031, -22.8327) -> (178.832, -22.8327)
  line L848 (74.0572, -41.8828) -> (74.0572, -39.8838)
  line L849 (74.0572, -39.8838) -> (88.0565, -39.8838)
  line L850 (88.0565, -39.8838) -> (88.0565, -41.8828)
  line L851 (88.0565, -41.8828) -> (88.8559, -41.8828)
  line L852 (88.8559, -41.8828) -> (88.8559, -44.9834)
  line L853 (88.8559, -44.9834) -> (88.0565, -44.9834)
  line L854 (88.0565, -44.9834) -> (88.0565, -50.7834)
  line L855 (88.0565, -50.7834) -> (88.8559, -50.7834)
  line L856 (88.8559, -50.7834) -> (88.8559, -53.8826)
  line L857 (88.8559, -53.8826) -> (88.0565, -53.8826)
  line L858 (88.0565, -53.8826) -> (88.0565, -55.8831)
  line L859 (88.0565, -55.8831) -> (74.0572, -55.8831)
  line L860 (74.0572, -55.8831) -> (74.0572, -53.8826)
  line L861 (74.0572, -53.8826) -> (73.2564, -53.8826)
  line L862 (73.2564, -53.8826) -> (73.2564, -50.7834)
  line L863 (73.2564, -50.7834) -> (74.0572, -50.7834)
  line L864 (74.0572, -50.7834) -> (74.0572, -44.9834)
  line L865 (74.0572, -44.9834) -> (73.2564, -44.9834)
  line L866 (73.2564, -44.9834) -> (73.2564, -41.8828)
  line L867 (73.2564, -41.8828) -> (74.0572, -41.8828)
  line L868 (121.682, -22.8327) -> (121.682, -20.8336)
  line L869 (121.682, -20.8336) -> (135.682, -20.8336)
  line L870 (135.682, -20.8336) -> (135.682, -22.8327)
  line L871 (135.682, -22.8327) -> (136.481, -22.8327)
  line L872 (136.481, -22.8327) -> (136.481, -25.9333)
  line L873 (136.481, -25.9333) -> (135.682, -25.9333)
  line L874 (135.682, -25.9333) -> (135.682, -31.7348)
  line L875 (135.682, -31.7348) -> (136.481, -31.7348)
  line L876 (136.481, -31.7348) -> (136.481, -34.8327)
  line L877 (136.481, -34.8327) -> (135.682, -34.8327)
  line L878 (135.682, -34.8327) -> (135.682, -36.833)
  line L879 (135.682, -36.833) -> (121.682, -36.833)
  line L880 (121.682, -36.833) -> (121.682, -34.8327)
  line L881 (121.682, -34.8327) -> (120.881, -34.8327)
  line L882 (120.881, -34.8327) -> (120.881, -31.7348)
  line L883 (120.881, -31.7348) -> (121.682, -31.7348)
  line L884 (121.682, -31.7348) -> (121.682, -25.9333)
  line L885 (121.682, -25.9333) -> (120.881, -25.9333)
  line L886 (120.881, -25.9333) -> (120.881, -22.8327)
  line L887 (120.881, -22.8327) -> (121.682, -22.8327)
  line L888 (55.0072, -41.8828) -> (55.0072, -39.8838)
  line L889 (55.0072, -39.8838) -> (69.0065, -39.8838)
  line L890 (69.0065, -39.8838) -> (69.0065, -41.8828)
  line L891 (69.0065, -41.8828) -> (69.8059, -41.8828)
  line L892 (69.8059, -41.8828) -> (69.8059, -44.9834)
  line L893 (69.8059, -44.9834) -> (69.0065, -44.9834)
  line L894 (69.0065, -44.9834) -> (69.0065, -50.7834)
  line L895 (69.0065, -50.7834) -> (69.8059, -50.7834)
  line L896 (69.8059, -50.7834) -> (69.8059, -53.8826)
  line L897 (69.8059, -53.8826) -> (69.0065, -53.8826)
  line L898 (69.0065, -53.8826) -> (69.0065, -55.8831)
  line L899 (69.0065, -55.8831) -> (55.0072, -55.8831)
  line L900 (55.0072, -55.8831) -> (55.0072, -53.8826)
  line L901 (55.0072, -53.8826) -> (54.2064, -53.8826)
  line L902 (54.2064, -53.8826) -> (54.2064, -50.7834)
  line L903 (54.2064, -50.7834) -> (55.0072, -50.7834)
  line L904 (55.0072, -50.7834) -> (55.0072, -44.9834)
  line L905 (55.0072, -44.9834) -> (54.2064, -44.9834)
  line L906 (54.2064, -44.9834) -> (54.2064, -41.8828)
  line L907 (54.2064, -41.8828) -> (55.0072, -41.8828)
  line L908 (221.695, -60.9328) -> (221.695, -58.9338)
  line L909 (221.695, -58.9338) -> (235.694, -58.9338)
  line L910 (235.694, -58.9338) -> (235.694, -60.9328)
  line L911 (235.694, -60.9328) -> (236.495, -60.9328)
  line L912 (236.495, -60.9328) -> (236.495, -64.0334)
  line L913 (236.495, -64.0334) -> (235.694, -64.0334)
  line L914 (235.694, -64.0334) -> (235.694, -69.8334)
  line L915 (235.694, -69.8334) -> (236.495, -69.8334)
  line L916 (236.495, -69.8334) -> (236.495, -72.9326)
  line L917 (236.495, -72.9326) -> (235.694, -72.9326)